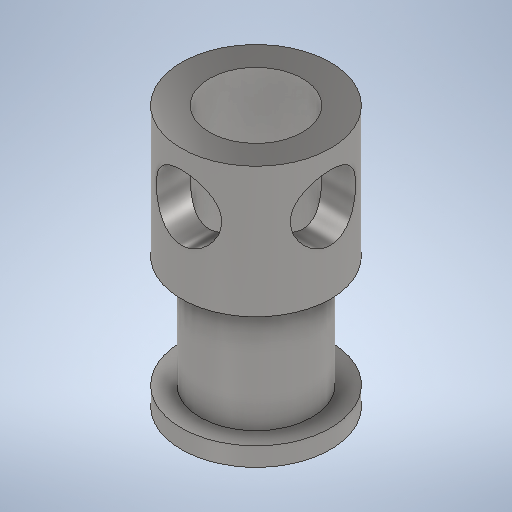
# Autodesk Inventor part: 타이밍벨트 풀리
Saved by Autodesk Inventor 2025.3 (Build 293356030, 356C)
## iProperties
Created: 2025-09-09
Part Number: 타이밍벨트 풀리
Material: 스테인리스스틸
Document SubType Name: Modeling
Designer: work
Density: 8 g/cm^3
Appearance: 반연마
Author: work
Autodesk Inventor part; units mm, degrees
ref_plane "XZ Plane" through (0, 0, 0) normal (0, 1, 0) x (-1, 0, 0)
ref_plane "XY Plane" through (0, 0, 0) normal (0, 0, 1) x (1, 0, 0)
sketch "스케치1" plane through (0, 0, 0) normal (0, 1, 0) x (-1, 0, 0)
  circle A0 centre (0, 0) radius 2.5
  circle A1 centre (0, 0) radius 4
  dimension "d0" = 5
  dimension "d1" = 8
  constraints: 2 centre point, 2 coincident
  measures "d0" diameter of A0
  measures "d1" diameter of A1
extrude "돌출1" add sketch "스케치1" along normal blind 1
sketch "스케치2" plane through (0, 1, 0) normal (0, 1, 0) x (1, 0, 0)
  circle A0 centre (0, 0) radius 3
  circle A1 centre (0, 0) radius 2.5
  dimension "d4" = 6
  constraints: 2 centre point, 2 coincident
  measures "d4" diameter of A0
extrude "돌출2" add sketch "스케치2" along normal blind 6
sketch "스케치3" plane through (0, 7, 0) normal (0, 1, 0) x (1, 0, 0)
  circle A0 centre (0, 0) radius 3 projected
  circle A1 centre (0, 0) radius 2.5 projected
  circle A2 centre (0, 0) radius 3 projected
  circle A3 centre (0, 0) radius 4 projected
  circle A4 centre (0, 0) radius 2.5
  circle A5 centre (0, 0) radius 4
  constraints: 2 centre point, 2 coincident, 2 concentric
extrude "돌출3" add sketch "스케치3" along normal blind 7 contours A0 | A3
ref_plane "작업 평면1" through (4, 7, 0) normal (1, 0, 0) x (0, 1, 0)
sketch "스케치4" plane through (4, 7, 0) normal (1, 0, 0) x (0, 1, 0)
  circle A0 centre (4.25, 0) radius 1.75
  line L0 (4.25, 0) -> (7, 0) construction
  line L1 (7, 2.5) -> (7, -2.5) projected
  point P0 (-7, 0)
  dimension "d9" = 3.5
  dimension "d10" = 1
  constraints: 2 end point, 1 centre point, 1 horizontal, 1 midpoint
  measures "d9" diameter of A0
  measures "d10" distance edge to line of A0 L1
extrude "돌출4" cut sketch "스케치4" against normal blind 3
pattern_circular "원형 패턴1" count 4 over 360 about axis through (0, 7, 0) along (0, 1, 0) of "돌출4" skipped copies 2 3
